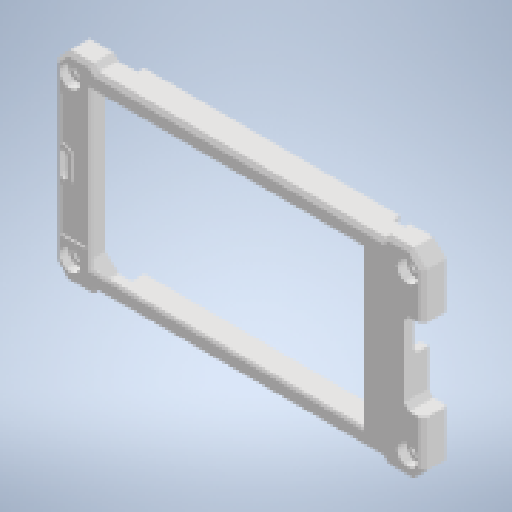
# Autodesk Inventor part: Cadre V4
Saved by Autodesk Inventor 2024 (Build 280153000, 153)
## iProperties
Created: 2026-10-31
Part Number: Cadre V4
Material: Générique
Document SubType Name: Modeling
Designer: berno
Density: 1 g/cm^3
Appearance: Par défaut
Author: berno
Autodesk Inventor part; units mm, degrees
sketch "Esq Cadre" plane through (0, 0, 0) normal (0, 0, 1) x (1, 0, 0)
  line L0 (72, -34) -> (72, 34)
  line L1 (72, 34) -> (67, 39)
  line L2 (67, 39) -> (58, 39)
  line L3 (58, 39) -> (56, 37)
  line L4 (56, 37) -> (-56, 37)
  line L5 (-56, 37) -> (-58, 39)
  line L6 (-58, 39) -> (-67, 39)
  line L7 (-67, 39) -> (-72, 34)
  line L8 (-72, 34) -> (-72, -34)
  line L9 (-72, -34) -> (-67, -39)
  line L10 (-67, -39) -> (-58, -39)
  line L11 (-58, -39) -> (-56, -37)
  line L12 (-56, -37) -> (56, -37)
  line L13 (56, -37) -> (58, -39)
  line L14 (58, -39) -> (67, -39)
  line L15 (67, -39) -> (72, -34)
  constraints: 32 end point
extrude "Cadre" add sketch "Esq Cadre" along normal blind 9.5
sketch "Esq Cavite" plane through (0, 0, 0) normal (0, 0, 1) x (1, 0, 0)
  line L0 (-61.5, -30.5) -> (-61.5, 30.5)
  line L1 (-61.5, 30.5) -> (-56.5, 35.5)
  line L2 (-56.5, 35.5) -> (56.5, 35.5)
  line L3 (56.5, 35.5) -> (61.5, 30.5)
  line L4 (61.5, 30.5) -> (61.5, -30.5)
  line L5 (61.5, -30.5) -> (56.5, -35.5)
  line L6 (56.5, -35.5) -> (-56.5, -35.5)
  line L7 (-56.5, -35.5) -> (-61.5, -30.5)
  constraints: 16 end point
extrude "Cavite" cut sketch "Esq Cavite" along normal blind 8.5
ref_plane "Plan de construction1" through (0, 0, 9.5) normal (0, 0, 1) x (1, 0, 0)
sketch "Esq Fenetre ecran" plane through (0, 0, 9.5) normal (0, 0, 1) x (1, 0, 0)
  line L0 (-58, -30.5) -> (48, -30.5)
  line L1 (48, -30.5) -> (48, 30.5)
  line L2 (48, 30.5) -> (-58, 30.5)
  line L3 (-58, 30.5) -> (-58, -30.5)
  constraints: 8 end point, 2 parallel, 1 horizontal, 1 perpendicular
extrude "Fenetre ecran" cut sketch "Esq Fenetre ecran" against normal blind 1.5
chamfer "Chanfrein avant" distance 1.4 angle 45 16 edges at (69.5, -36.5, 9.5) (62.5, -39, 9.5) (57, -38, 9.5) (0, -37, 9.5) (-57, -38, 9.5) (-62.5, -39, 9.5) (-69.5, -36.5, 9.5) (-72, 0, 9.5) (-69.5, 36.5, 9.5) (-62.5, 39, 9.5) (-57, 38, 9.5) (0, 37, 9.5) (57, 38, 9.5) (62.5, 39, 9.5) (69.5, 36.5, 9.5) (72, 0, 9.5)
chamfer "Chanfrein fenetre" distance 0.8 angle 45 4 edges at (48, 0, 9.5) (-5, -30.5, 9.5) (-58, 0, 9.5) (-5, 30.5, 9.5)
chamfer "Chanfrein plafond" distance 1.4 angle 45 8 edges at (-59, 33, 8.5) (0, 35.5, 8.5) (59, 33, 8.5) (61.5, 0, 8.5) (59, -33, 8.5) (0, -35.5, 8.5) (-59, -33, 8.5) (-61.5, 0, 8.5)
ref_plane "Plan de construction2" through (0, 0, 9.5) normal (0, 0, 1) x (1, 0, 0)
sketch "Esq Creux haut et menton" plane through (0, 0, 9.5) normal (0, 0, 1) x (1, 0, 0)
  line L0 (-69.6, -24) -> (-59.6, -24)
  line L1 (-59.6, -24) -> (-59.6, 24)
  line L2 (-59.6, 24) -> (-69.6, 24)
  line L3 (-69.6, 24) -> (-69.6, -24)
  constraints: 8 end point, 2 parallel, 1 horizontal, 1 perpendicular
extrude "Creux haut et menton" cut sketch "Esq Creux haut et menton" against normal blind 0.6
ref_plane "Plan de construction3" through (0, 0, 9.5) normal (0, 0, 1) x (1, 0, 0)
sketch "Esq Trous vis M4" plane through (0, 0, 9.5) normal (0, 0, 1) x (1, 0, 0)
  circle A0 centre (66, 31) radius 2.25
  circle A1 centre (66, -31) radius 2.25
  circle A2 centre (-66, 31) radius 2.25
  circle A3 centre (-66, -31) radius 2.25
  constraints: 4 centre point
extrude "Trous vis M4" cut sketch "Esq Trous vis M4" against normal blind 10.5
ref_plane "Plan de construction4" through (0, 0, 9.5) normal (0, 0, 1) x (1, 0, 0)
sketch "Esq Lamages vis" plane through (0, 0, 9.5) normal (0, 0, 1) x (1, 0, 0)
  circle A0 centre (66, 31) radius 4
  circle A1 centre (66, -31) radius 4
  circle A2 centre (-66, 31) radius 4
  circle A3 centre (-66, -31) radius 4
  constraints: 4 centre point
extrude "Lamages vis" cut sketch "Esq Lamages vis" against normal blind 3.5
sketch "Esq Encoche USB-C" plane through (0, 0, 0) normal (0, 0, 1) x (1, 0, 0)
  line L0 (72.5, -16) -> (66.5, -16)
  line L1 (66.5, -16) -> (64.5, -14)
  line L2 (64.5, -14) -> (64.5, 14)
  line L3 (64.5, 14) -> (66.5, 16)
  line L4 (66.5, 16) -> (72.5, 16)
  line L5 (72.5, 16) -> (72.5, -16)
  constraints: 12 end point
extrude "Encoche USB-C" cut sketch "Esq Encoche USB-C" along normal blind 10.5
ref_plane "Plan de construction5" through (63, 0, 0) normal (1, 0, 0) x (0, 1, 0)
sketch "Esq Ouverture USB-C" plane through (63, 0, 0) normal (1, 0, 0) x (0, 1, 0)
  line L0 (2, -2) -> (13, -2)
  line L1 (13, -2) -> (14.5, -0.5)
  line L2 (14.5, -0.5) -> (14.5, 4)
  line L3 (14.5, 4) -> (13, 5.5)
  line L4 (13, 5.5) -> (2, 5.5)
  line L5 (2, 5.5) -> (0.5, 4)
  line L6 (0.5, 4) -> (0.5, -0.5)
  line L7 (0.5, -0.5) -> (2, -2)
  constraints: 16 end point
extrude "Ouverture USB-C" cut sketch "Esq Ouverture USB-C" along normal mid plane 6
sketch "Esq Passant dragonne" plane through (0, 0, 0) normal (0, 0, 1) x (1, 0, 0)
  line L0 (-67, -3.5) -> (-67, 3.5)
  line L1 (-70, 3.5) -> (-70, -3.5)
  arc A0 (-67, 3.5) -> (-70, 3.5) centre (-68.5, 3.5) ccw
  arc A1 (-70, -3.5) -> (-67, -3.5) centre (-68.5, -3.5) ccw
  constraints: 4 end point, 4 point on circle, 2 centre point
extrude "Passant dragonne" cut sketch "Esq Passant dragonne" along normal blind 10.5
sketch "Esq Languette" plane through (0, 0, 0) normal (0, 0, 1) x (1, 0, 0)
  line L0 (-50, 34.15) -> (50, 34.15)
  line L1 (50, 34.15) -> (50, 35.35)
  line L2 (50, 35.35) -> (-50, 35.35)
  line L3 (-50, 35.35) -> (-50, 34.15)
  line L4 (-50, -35.35) -> (50, -35.35)
  line L5 (50, -35.35) -> (50, -34.15)
  line L6 (50, -34.15) -> (-50, -34.15)
  line L7 (-50, -34.15) -> (-50, -35.35)
  constraints: 16 end point, 4 parallel, 2 horizontal, 2 perpendicular
extrude "Languette" add sketch "Esq Languette" against normal blind 4
sketch "Esq Liaison languette" plane through (0, 0, 0) normal (0, 0, 1) x (1, 0, 0)
  line L0 (-50, 34.15) -> (50, 34.15)
  line L1 (50, 34.15) -> (50, 36)
  line L2 (50, 36) -> (-50, 36)
  line L3 (-50, 36) -> (-50, 34.15)
  line L4 (-50, -36) -> (50, -36)
  line L5 (50, -36) -> (50, -34.15)
  line L6 (50, -34.15) -> (-50, -34.15)
  line L7 (-50, -34.15) -> (-50, -36)
  constraints: 16 end point, 4 parallel, 2 horizontal, 2 perpendicular
extrude "Liaison languette" add sketch "Esq Liaison languette" along normal blind 9
chamfer "Chanfrein languette" distance 0.35 angle 45 8 edges at (0, 34.15, -4) (-50, 34.75, -4) (0, 35.35, -4) (50, 34.75, -4) (0, -35.35, -4) (-50, -34.75, -4) (0, -34.15, -4) (50, -34.75, -4)
sketch "Esq Ligne d'ombre" plane through (0, 0, 0) normal (0, 0, 1) x (1, 0, 0)
  line L0 (-80, -45) -> (80, -45)
  line L1 (80, -45) -> (80, 45)
  line L2 (80, 45) -> (-80, 45)
  line L3 (-80, 45) -> (-80, -45)
  line L4 (71.3, -33.71) -> (66.71, -38.3)
  line L5 (66.71, -38.3) -> (58.29, -38.3)
  line L6 (58.29, -38.3) -> (56.29, -36.3)
  line L7 (56.29, -36.3) -> (-56.29, -36.3)
  line L8 (-56.29, -36.3) -> (-58.29, -38.3)
  line L9 (-58.29, -38.3) -> (-66.71, -38.3)
  line L10 (-66.71, -38.3) -> (-71.3, -33.71)
  line L11 (-71.3, -33.71) -> (-71.3, 33.71)
  line L12 (-71.3, 33.71) -> (-66.71, 38.3)
  line L13 (-66.71, 38.3) -> (-58.29, 38.3)
  line L14 (-58.29, 38.3) -> (-56.29, 36.3)
  line L15 (-56.29, 36.3) -> (56.29, 36.3)
  line L16 (56.29, 36.3) -> (58.29, 38.3)
  line L17 (58.29, 38.3) -> (66.71, 38.3)
  line L18 (66.71, 38.3) -> (71.3, 33.71)
  line L19 (71.3, 33.71) -> (71.3, -33.71)
  constraints: 40 end point, 2 parallel, 1 horizontal, 1 perpendicular
extrude "Ligne d'ombre" cut sketch "Esq Ligne d'ombre" along normal blind 0.7
sketch "Esquisse13" plane through (0, 0, 8.9) normal (0, 0, 1) x (1, 0, 0)
  arc A0 (-67, 3.5) -> (-69.6, 4.5198) centre (-68.5, 3.5) ccw projected
  line L0 (-68.5441, 4.9994) -> (-68.5441, -4.9994)
  arc A1 (-69.6, -4.5198) -> (-67, -3.5) centre (-68.5, -3.5) ccw projected
  line L1 (-67, 3.5) -> (-67, -3.5) projected
  line L2 (-67, 0) -> (-70, 0)
  line L3 (-70, -3.5) -> (-70, 3.5) projected
  line L4 (-68.5, -3.5) -> (-68.5, 3.5) construction
  line L5 (-67, -3.5) -> (-67, 3.5)
  line L6 (-70, 3.5) -> (-70, -3.5)
  arc A2 (-70, -3.5) -> (-67, -3.5) centre (-68.5, -3.5) ccw
  arc A3 (-67, 3.5) -> (-70, 3.5) centre (-68.5, 3.5) ccw
  line L7 (-68.4559, -3.4985) -> (-68.5441, 3.4985) construction
  line L8 (-64.9564, -3.4545) -> (-65.0445, 3.5426)
  line L9 (-72.0436, 3.4545) -> (-71.9555, -3.5426)
  arc A4 (-71.9555, -3.5426) -> (-64.9564, -3.4545) centre (-68.4559, -3.4985) ccw
  arc A5 (-65.0445, 3.5426) -> (-72.0436, 3.4545) centre (-68.5441, 3.4985) ccw
  line L10 (-69.6, 4.5198) -> (-69.6, 24) projected
  line L11 (-69.6, 8.3809) -> (-69.6, -9.7828)
  point P0 (0, 0)
  point P1 (-68.5, 0)
  point P2 (-68.5881, 6.9981)
  point P3 (-68.5, 5)
  point P4 (-65.0005, 0.0441)
  point P5 (-67, 0)
  point P6 (69.6, 16)
  point P7 (64.5, 14)
  point P8 (66.5, -16)
  point P9 (64.5, -14)
  point P10 (69.6, -16)
  point P11 (-69.6, 6.8352)
  point P12 (-69.6, -6.8061)
  dimension "d41" = 2
  dimension "d42" = 2
  dimension "d43" = 0
  constraints: 22 end point, 12 point on circle, 8 tangent, 7 midpoint, 4 centre point, 3 parallel, 2 point on line, 1 collinear, 1 vertical
  measures "d41" distance of point (-68.588, 6.998) point (-68.5, 5)
  measures "d42" distance of point (-65, 0.044) point (-67, 0)
  measures "d43" distance between parallel lines of L1 L5
extrude "Extrusion13" add sketch "Esquisse13" along normal blind 0.6 contours A0 L10 A5 L8 A4 L11 A1 L1
